Metcal 910-N süstal 10cc (Autodesk Fusion 360 design; units mm, degrees)
Autodesk Fusion 360 part; units mm, degrees
sketch "Sketch1" plane through (0, 0, 0) normal (0, 0, 1) x (1, 0, 0)
  line L0 (9.075, 87.75) -> (9.075, 14.682)
  line L1 (5.31, 10.668) -> (5.31, 2.3)
  line L2 (6.0158, 11.9405) -> (8.3692, 13.4095)
  line L3 (2, 9.3) -> (2, 0)
  line L4 (2, 0) -> (0, 0) construction
  line L5 (1.2, 9.3) -> (1.2, 0.8)
  line L6 (1.2, 0.8) -> (0, 0.8) construction
  line L7 (1.2, 0.8) -> (1.2, 0)
  line L8 (2, 0) -> (1.2, 0)
  line L9 (3.51, 2.3) -> (5.31, 2.3)
  line L10 (2, 9.3) -> (3.51, 9.3)
  line L11 (5.0627, 13.4675) -> (1.2, 9.3)
  arc A0 (8.3692, 13.4095) -> (9.075, 14.682) centre (7.575, 14.682) ccw
  arc A1 (6.0158, 11.9405) -> (5.31, 10.668) centre (6.81, 10.668) ccw
  line L12 (7.275, 87.75) -> (7.275, 14.8483)
  line L13 (5.0627, 13.4675) -> (7.275, 14.8483)
  line L14 (3.51, 9.3) -> (3.51, 2.3)
  line L15 (7.275, 87.75) -> (9.075, 87.75)
  line L16 (0, 0) -> (0, 29) construction
  point P0 (9.075, 13.85)
  point P1 (5.31, 11.5)
  dimension "d1" = 73.9
  dimension "d2" = 76.25
  dimension "d3" = 9.075
  dimension "d4" = 5.31
  dimension "d5" = 85.45
  dimension "d7" = 2.3
  dimension "d8" = 2
  dimension "d9" = 9.3
  dimension "d10" = 0.8
  dimension "d13" = 1.5
  dimension "d14" = 1.5
  dimension "d15" = 87.75
  constraint vertical L0
  constraint vertical L1
  constraint parallel L1 L3
  constraint perpendicular L3 L4
  constraint coincident L4.end L16.start
  constraint coincident L4 L7.end
  constraint perpendicular L4 L7
  constraint perpendicular L1 L9
  constraint perpendicular L10 L14
  constraint coincident P0 L2
  constraint coincident P0 L0
  constraint tangent L2 A0
  constraint tangent L0 A0
  constraint coincident P1 L1
  constraint coincident P1 L2
  constraint tangent L1 A1
  constraint tangent L2 A1
  constraint perpendicular L0 L15
  constraint perpendicular L6 L16
  measures "d1" distance of L0.start P0
  measures "d2" vertical distance of L0.start P1
  measures "d3" distance of L4.end L0
  measures "d4" distance of L4.end L1
  measures "d5" vertical distance of L0.start L1.end
  measures "d7" vertical distance of L1.end L3.end
  measures "d8" distance of L4.end L3
  measures "d9" distance of L3.start L3.end
  measures "d13" radius of A0
  measures "d14" radius of A1
  measures "d15" vertical distance of L0.start L3.end
revolve "Revolve1" add sketch "Sketch1" angle 360 about axis through (0, 0, 0) along (0, 1, 0)
sketch "Sketch2" plane through (0, 87.75, 0) normal (0, 1, 0) x (-1, 0, 0)
  circle A0 centre (0, 0) radius 7.275
  circle A1 centre (0, 0) radius 9.075
  line L0 (-8.42, -11.27) -> (8.42, -11.27)
  line L1 (8.42, -11.27) -> (8.42, 11.27)
  line L2 (8.42, 11.27) -> (-8.42, 11.27)
  line L3 (-8.42, 11.27) -> (-8.42, -11.27)
  line L4 (-8.42, -11.27) -> (8.42, 11.27) construction
  line L5 (8.42, -11.27) -> (-8.42, 11.27) construction
  line L6 (0, 0) -> (-17, 0) construction
  line L7 (0, 0) -> (17, 0) construction
  line L8 (8.42, -11.27) -> (14.8679, -5.0303)
  line L9 (14.8679, 5.0303) -> (8.42, 11.27)
  arc A2 (14.8679, -5.0303) -> (14.8679, 5.0303) centre (10, 0) ccw
  line L10 (0, 0) -> (0, -20)
  line L11 (-8.42, -11.27) -> (-14.8679, -5.0303)
  arc A3 (-14.8679, 5.0303) -> (-14.8679, -5.0303) centre (-10, 0) ccw
  line L12 (-14.8679, 5.0303) -> (-8.42, 11.27)
  circle A4 centre (0, 0) radius 7.275
  dimension "d17" = 22.54
  dimension "d18" = 16.84
  dimension "d19" = 17
  dimension "d20" = 17
  dimension "d22" = 7
  constraint horizontal L0
  constraint perpendicular L0 L1
  constraint parallel L0 L2
  constraint parallel L1 L3
  constraint coincident L4 A0.centre
  constraint coincident L5 A0.centre
  constraint coincident A0.centre A1.centre
  constraint horizontal L6
  constraint parallel L6 L7
  constraint tangent L8 A2
  constraint tangent L9 A2
  constraint coincident L7 A2.centre
  constraint perpendicular L0 L10
  constraint symmetric L0.end L10 L0.start
  constraint symmetric L1.end L10 L2.end
  constraint symmetric L8.end L10 L11.end
  constraint symmetric L9.start L10 A3.start
  constraint symmetric A2 L10 A3
  measures "d17" distance of L0 L2
  measures "d18" distance of L1 L3
  measures "d19" distance of A0.centre L6.end
  measures "d20" distance of A0.centre L7.end
  measures "d22" radius of A2
extrude "Extrude1" add sketch "Sketch2" along normal blind 3.34
sketch "Sketch3" plane through (0, 0, 11.27) normal (0, 0, 1) x (1, 0, 0)
  line L0 (-8.42, 87.75) -> (8.42, 87.75)
  line L1 (8.42, 87.75) -> (8.42, 91.09)
  line L2 (8.42, 91.09) -> (-8.42, 91.09)
  line L3 (-8.42, 91.09) -> (-8.42, 87.75)
  line L4 (-8.42, 91.09) -> (8.42, 91.09)
  line L5 (8.42, 91.09) -> (14.8679, 91.09)
  line L6 (17, 91.09) -> (14.8679, 91.09)
  line L7 (-14.8679, 91.09) -> (-8.42, 91.09)
  line L8 (-14.8679, 91.09) -> (-17, 91.09)
  line L9 (-17, 91.09) -> (-17, 88.99)
  line L10 (17, 91.09) -> (17, 88.99)
  line L11 (14.8679, 87.75) -> (8.42, 87.75)
  line L12 (-14.8679, 87.75) -> (-8.42, 87.75)
  line L13 (17, 88.99) -> (12.5, 87.75)
  line L14 (-17, 88.99) -> (-12.5, 87.75)
  line L15 (12.5, 87.75) -> (18, 87.75)
  line L16 (18, 87.75) -> (18, 91)
  line L17 (18, 91) -> (17, 91.09)
  line L18 (-17, 91.09) -> (-18, 91.09)
  line L19 (-18, 91.09) -> (-18, 87.4051)
  line L20 (-18, 87.4051) -> (-12.5, 87.4051)
  line L21 (-12.5, 87.4051) -> (-12.5, 87.75)
  dimension "d25" = 2.1
  dimension "d26" = 2.1
  dimension "d27" = 4.5
  dimension "d28" = 4.5
  constraint coincident L8.end L9.start
  constraint perpendicular L8 L9
  constraint coincident L6.start L10.start
  constraint perpendicular L6 L10
  constraint coincident L11 L13.end
  constraint coincident L12 L14.end
  constraint parallel L11 L15
  constraint perpendicular L15 L16
  constraint perpendicular L9 L18
  constraint perpendicular L18 L19
  constraint perpendicular L19 L20
  constraint parallel L19 L21
  measures "d25" distance of L8.end L9.end
  measures "d26" distance of L6.start L10.end
  measures "d27" horizontal distance of L9.end L14.end
  measures "d28" horizontal distance of L10.end L13.end
extrude "Extrude2" cut sketch "Sketch3" against normal blind 68 contours L9 L14 L18 L19 L20 L21 | L10 L11 L13 L15 L16 L17
fillet "Fillet1" radius 1 1 edges at (-8.4609, 87.75, -3.2817)
fillet "Fillet2" radius 0.8 11 edges at (0, 87.75, 11.27) (10.46, 87.75, 9.2959) (13.6839, 88.0762, 6.176) (17, 88.99, 0) (13.6839, 88.0762, -6.176) (10.46, 87.75, -9.2959) (0, 87.75, -11.27) (-10.46, 87.75, -9.2959) (-13.6839, 88.0762, -6.176) (-17, 88.99, 0) (-13.6839, 88.0762, 6.176)
equation "d3 = ( 18.15 / 2 ) * 1 mm"
equation "d4 = ( 10.62 / 2 ) * 1 mm"
equation "d28 = d27"
